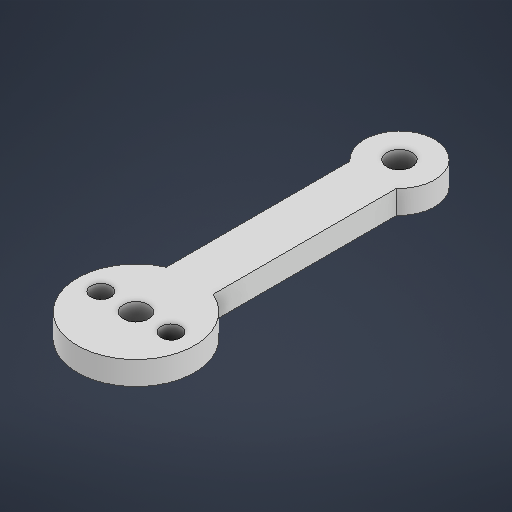
# Autodesk Inventor part: UpperCrankline
Saved by Autodesk Inventor 2027 (Build 310192000, 192)
## iProperties
Created: 2026-10-23
Part Number: UpperCrankline
Material: Generic
Document SubType Name: Modeling
Designer: HP
Density: 1 g/cm^3
Appearance: Default
Author: HP
Autodesk Inventor part; units mm, degrees
ref_plane "YZ Plane" through (0, 0, 0) normal (1, 0, 0) x (0, 1, 0)
ref_plane "XZ Plane" through (0, 0, 0) normal (0, 1, 0) x (-1, 0, 0)
ref_plane "XY Plane" through (0, 0, 0) normal (0, 0, 1) x (1, 0, 0)
sketch "Sketch1" plane through (0, 0, 0) normal (0, 1, 0) x (-1, 0, 0)
  line L0 (4, -19.1652) -> (4, -50.5279)
  line L1 (-4, -50.5279) -> (-4, -19.1652)
  arc A0 (-4, -50.5279) -> (4, -50.5279) centre (0, -55) ccw
  arc A1 (4, -19.1652) -> (-4, -19.1652) centre (0, -10) ccw
  circle A2 centre (0, -55) radius 2.15
  circle A3 centre (0, -10) radius 2.15
  circle A4 centre (6, -10) radius 1.7
  circle A5 centre (-6, -10) radius 1.7
  point P0 (0, 0)
  point P1 (0, 0)
  point P2 (0, 0)
  dimension "d4" = 6
  dimension "d5" = 8
  dimension "d6" = 10
  dimension "d19" = 4.3
  dimension "d20" = 4.3
  dimension "d23" = 3.4
  dimension "d24" = 3.4
  dimension "d25" = 12
  dimension "d26" = 6
  dimension "d27" = 6
  dimension "d31" = 45
  constraints: 6 centre point, 5 point on circle, 4 coincident, 4 end point, 2 parallel, 1 horizontal alignment, 1 vertical, 1 vertical alignment
  measures "d4" radius of A0
  measures "d5" distance of L1.start L0.end
  measures "d6" radius of A1
  measures "d19" diameter of A2
  measures "d20" diameter of A3
  measures "d23" diameter of A4
  measures "d24" diameter of A5
  measures "d25" distance of A4.centre A5.centre
  measures "d26" distance of A3.centre A5.centre
  measures "d27" distance of A3.centre A4.centre
  measures "d31" distance of A1.centre A0.centre
extrude "Extrusion4" add sketch "Sketch1" against normal blind 4
body "Solid3"
